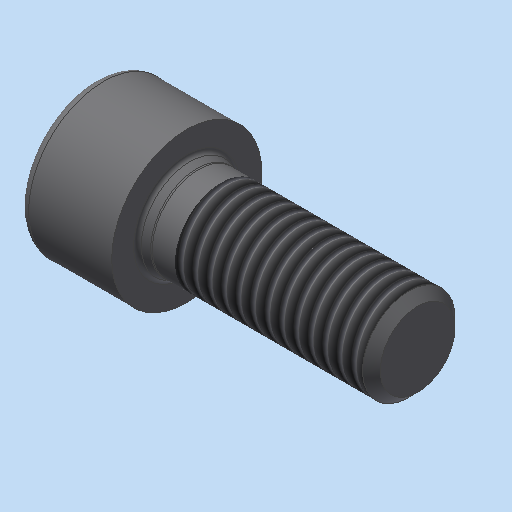
# Autodesk Inventor part: Zylinderschraube_ISO_4762___M8x20
Saved by Autodesk Inventor 2023.3 (Build 273359000, 359)
## iProperties
Shininess: 64.0
Length Units: 11269
Angle Units: 11279
Time Units: 11290
Mass Units: 11283
Length Display Precision: 3
Angle Display Precision: 2
Compacted: True
Part Number: Zylinderschraube_ISO_4762___M8x20
Document SubType Name: Modeling
Created: 2004-04-03
Material: xStahl_AnP_Dummymaterial
Description: =<RBPARTNOTITLE2>
Vendor: NORM8
Designer: S.Riedelsheimer
Manufacturer: Standard
Standards Organization: Custom
Density: 7.85 g/cm^3
Appearance: Stahl - normal AnP
Mass: 14.8773 g
Surface Area: 11.5931 cm^2
Volume: 1.8952 cm^3
Density: 0.0
Volumn: 0.0
Area: 0.0
PropertySet Name: Model Information
Control State: 0
Master: False
Checked Out: False
CNS_NB: Zylinderschraube ISO 4762 - M8x20
CNS_NN: ISO 4762
CNS_NT: Zylinderschrauben mit Innensechskant
CNS_NBSYN: Zylinderschraube ISO 4762 - $NENN.
CNS_LINA: Zylinderschraube ISO 4762 - M8x20
CNS_D: 8.000
CNS_D3: 6.466
CNS_P: 1.250
CNS_L: 20.000
CNS_S: 6.000
CNS_HM: 20.000
CNS_DK: 13.000
CNS_DA: 9.200
CNS_DS: 8.000
CNS_E: 6.860
CNS_K: 8.000
CNS_R: 0.400
CNS_T: 4.000
CNS_V: 0.800
CNS_DW: 12.330
CNS_W: 3.300
CNS_LF: 1.020
CNS_LG: 3.750
CNS_FORM: 1.000
CNS_NENN: M8x20
CNS_KT: DUMMY
PSOL_IDENT_0: {C:\partsolutions8\data\23d-libs\bosch_bamberg\schrauben\zylinderschrauben\din_en_iso_4762.prj},170
PSOL_IDENT_1: {M=Nenngewinde},{VTYP=3D},{NB=Zylinderschraube ISO 4762 - M8x20},{NN=ISO 4762},{DATE=26.11.2003},{GE
PSOL_IDENT_2: OMDATE=26.11.2003},{VERSION=v2},{LINEID=720},{LINESUBID=-1},{WBVAR=}  {NB=Zylinderschraube ISO 4762
PSOL_IDENT_3: - M8x20},{LINA=Zylinderschraube ISO 4762 - M8x20},{KT=DUMMY},{IDNR=},{D=8.000},{D3=6.466},{P=1.250},
PSOL_IDENT_4: {L=20.000},{S=6.000},{HM=20.000},{DK=13.000},{DA=9.200},{DS=8.000},{E=6.860},{K=8.000},{R=0.400},{T=
PSOL_IDENT_5: 4.000},{V=0.800},{DW=12.330},{W=3.300},{LF=1.020},{LG=3.750},{FORM=1.000},{NENN=M8x20}
RBPARTNOTITLE2: Zylinderschrauben mit Innensechskant
RBPARTNOTITLE1: Hexagon socket head cap screws
AnP_Kategorie: 4
RBDRAWINGMISSINGSPEC: --
RBPARTMADEOF: ISO 4762 - M8x20 - 8.8 verzinkt
Title: Zylinderschraube ISO 4762 - M8x20
Author: S.Riedelsheimer
Keywords: =<RBPARTMADEOF>
Comments: =<RBSURFACE2>
Revision Number: 01
Autodesk Inventor part; units mm, degrees
sketch "Skizze_2" plane through (0, 0, 0) normal (0, 0, 1) x (1, 0, 0)
  line L0 (23, 0) -> (-11, 0)
  line L1 (-1.5679, 0) -> (-3.3, 3)
  line L2 (-3.3, 3) -> (-7.57, 3)
  line L3 (-7.57, 3) -> (-8, 3.43)
  line L4 (-8, 3.43) -> (-8, 5.7)
  arc A0 (-7.2, 6.5) -> (-8, 5.7) centre (-7.2, 5.7) ccw
  line L5 (-7.2, 6.5) -> (0, 6.5)
  line L6 (0, 6.5) -> (0, 4.6)
  arc A1 (0, 4.6) -> (0.2772, 4.2193) centre (0.4, 4.6) ccw
  line L7 (0.2772, 4.2193) -> (0.8972, 4.0193)
  arc A2 (0.8972, 4.0193) -> (1.02, 4) centre (1.02, 4.4) ccw
  line L8 (1.02, 4) -> (19.233, 4)
  line L9 (19.233, 4) -> (20, 3.233)
  line L10 (20, 3.233) -> (20, 0)
  line L11 (20, 0) -> (-1.5679, 0)
  constraints: 24 end point, 6 point on circle, 3 centre point
revolve "Drehung1" add sketch "Skizze_2" angle 360 about axis through (23, 0, 0) along (1, 0, 0)
thread "Gewinde1" size "M8x1.25" class "6g" standard "ANSI Metric M Profile" length 16.25
sketch "Skizze_1" plane through (-3.3, 0, 0) normal (1, 0, 0) x (0, 0, -1)
  line L0 (-3, 1.7321) -> (-3, -1.7321)
  line L1 (-3, -1.7321) -> (0, -3.4641)
  line L2 (0, -3.4641) -> (3, -1.7321)
  line L3 (3, -1.7321) -> (3, 1.7321)
  line L4 (3, 1.7321) -> (0, 3.4641)
  line L5 (0, 3.4641) -> (-3, 1.7321)
  constraints: 12 end point
extrude "Extrusion1" cut sketch "Skizze_1" against normal blind 8
ref_plane "IP1_XY" through (0, 0, 0) normal (1, 0, 0) x (0, 0, -1)
ref_plane "IP1_YZ" through (0, 0, 0) normal (0, 0, -1) x (0, 1, 0)
ref_plane "IP3_XY" through (20, 0, 0) normal (1, 0, 0) x (0, 0, -1)
ref_plane "IP3_YZ" through (20, 0, 0) normal (0, 0, -1) x (0, 1, 0)
ref_plane "IP2_XY" through (-8, 0, 0) normal (1, 0, 0) x (0, 0, -1)
ref_plane "IP2_YZ" through (-8, 0, 0) normal (0, 0, -1) x (0, 1, 0)
